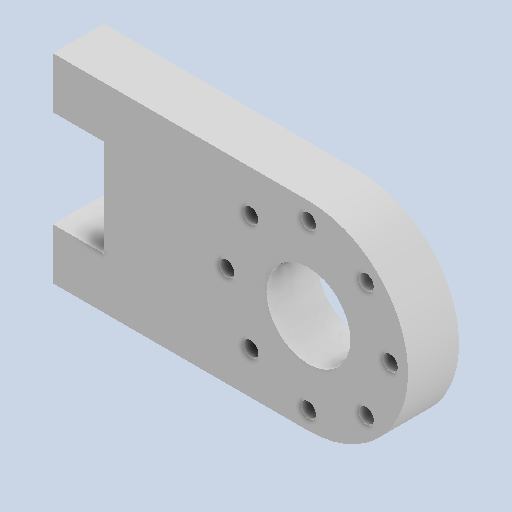
# Autodesk Inventor part: NeckConnectSide
Saved by Autodesk Inventor 2025.2 (Build 292293000, 293)
## iProperties
Created: 2025-06-29
Part Number: NeckConnectSide
Material: Generic
Document SubType Name: Modeling
Designer: ricoa
Density: 1 g/cm^3
Appearance: Default
Author: ricoa
Autodesk Inventor part; units mm, degrees
ref_plane "YZ Plane" through (0, 0, 0) normal (1, 0, 0) x (0, 1, 0)
ref_plane "XZ Plane" through (0, 0, 0) normal (0, 1, 0) x (-1, 0, 0)
ref_plane "XY Plane" through (0, 0, 0) normal (0, 0, 1) x (1, 0, 0)
sketch "Sketch1" plane through (0, 0, 0) normal (0, 0, 1) x (1, 0, 0)
  arc A0 (0, -9.75) -> (0, 9.75) centre (0, 0) ccw
  circle A1 centre (0, 0) radius 4 projected
  circle A2 centre (-5.6569, 5.6569) radius 0.75 projected
  circle A3 centre (-8, 0) radius 0.75 projected
  circle A4 centre (-5.6569, -5.6569) radius 0.75 projected
  circle A5 centre (0, -8) radius 0.75 projected
  circle A6 centre (5.6569, -5.6569) radius 0.75 projected
  circle A7 centre (8, 0) radius 0.75 projected
  circle A8 centre (5.6569, 5.6569) radius 0.75 projected
  circle A9 centre (0, 8) radius 0.75 projected
  circle A10 centre (0, 0) radius 4.1
  line L0 (0, 9.75) -> (-20, 9.75)
  line L1 (-20, 9.75) -> (-25, 9.75)
  line L2 (-25, 9.75) -> (-25, 4.75)
  line L3 (-25, 4.75) -> (-20, 4.75)
  line L4 (-20, 4.75) -> (-20, 0)
  line L5 (0, 0) -> (-20, 0) construction
  line L6 (0, -9.75) -> (-20, -9.75)
  line L7 (-20, -9.75) -> (-25, -9.75)
  line L8 (-25, -9.75) -> (-25, -4.75)
  line L9 (-25, -4.75) -> (-20, -4.75)
  line L10 (-20, -4.75) -> (-20, 0)
  point P0 (0, 0)
  dimension "d0" = 8.2
  dimension "d1" = 20
  dimension "d2" = 5
  dimension "d3" = 5
  constraints: 22 end point, 5 symmetric about line, 3 perpendicular, 2 centre point, 2 horizontal, 2 point on circle, 2 point on line, 1 coincident, 1 tangent
  measures "d0" diameter of A10
  measures "d1" distance of L0.start L0.end
  measures "d2" distance of L0.end L1.end
  measures "d3" distance of L1.end L2.end
extrude "Extrusion1" add sketch "Sketch1" along normal blind 5 contours L6 L7 L8 L9 L10 L4 L3 L2 L1 L0 A0
body "Solid1"
